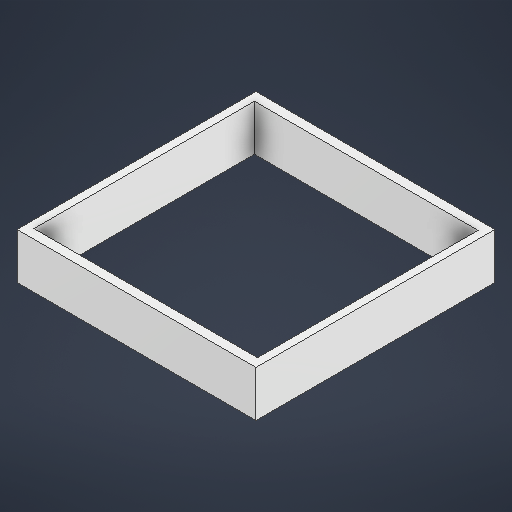
# Autodesk Inventor part: Крепление_свича
Saved by Autodesk Inventor 2026 (Build 300175050, 175E)
## iProperties
Created: 2026-10-25
Part Number: Крепление_свича
Material: Пластик АБС
Document SubType Name: Modeling
Designer: VK7
Density: 1.06 g/cm^3
Appearance: Гладкий — белый
Author: VK7
Autodesk Inventor part; units mm, degrees
ref_plane "YZ Plane" through (0, 0, 0) normal (1, 0, 0) x (0, 1, 0)
ref_plane "XZ Plane" through (0, 0, 0) normal (0, 1, 0) x (-1, 0, 0)
ref_plane "XY Plane" through (0, 0, 0) normal (0, 0, 1) x (1, 0, 0)
sketch "Эскиз1" plane through (0, 0, 0) normal (0, 1, 0) x (-1, 0, 0)
  line L0 (0, 0) -> (15.6, 0)
  line L1 (15.6, 0) -> (15.6, -15.6)
  line L2 (15.6, -15.6) -> (0, -15.6)
  line L3 (0, -15.6) -> (0, 0)
  line L4 (0, 0) -> (0, -0.6)
  line L5 (0, -0.6) -> (0.5, -0.6)
  line L6 (15.6, -15.6) -> (15.1, -15.6)
  line L7 (15.1, -15.6) -> (15.1, -15)
  line L8 (15.1, -15) -> (0.5, -15)
  line L9 (0.5, -15) -> (0.5, -0.6)
  line L10 (0.5, -0.6) -> (15.1, -0.6)
  line L11 (15.1, -0.6) -> (15.1, -15)
  dimension "d0" = 15.6
  dimension "d1" = 15.6
  dimension "d2" = 0.6
  dimension "d3" = 0.5
  dimension "d4" = 0.5
  dimension "d5" = 0.6
  constraints: 24 end point, 4 parallel, 4 perpendicular, 2 horizontal, 2 point on line
  measures "d0" distance of L1.end L2.end
  measures "d1" distance of L0.end L1.end
  measures "d2" distance of L0.start L4.end
  measures "d3" distance of L4.end L5.end
  measures "d4" distance of L1.end L6.end
  measures "d5" distance of L6.end L7.end
extrude "Выдавливание1" add sketch "Эскиз1" along normal blind 3 contours L0 L1 L2 L7 L11 L10 L5 L3 | L5 L9 L8 L7 L2 L3
